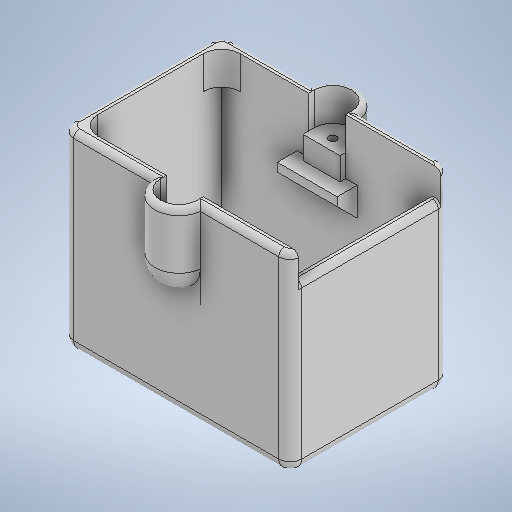
# Autodesk Inventor part: Lehmän laturi
Saved by Autodesk Inventor 2025.1 (Build 291241000, 241)
## iProperties
Created: 2025-09-19
Part Number: Lehmän laturi
Material: Generic
Document SubType Name: Modeling
Designer: totoikka
Density: 1 g/cm^3
Appearance: Default
Author: totoikka
Autodesk Inventor part; units mm, degrees
ref_plane "YZ Plane" through (0, 0, 0) normal (1, 0, 0) x (0, 1, 0)
ref_plane "XZ Plane" through (0, 0, 0) normal (0, 1, 0) x (-1, 0, 0)
ref_plane "XY Plane" through (0, 0, 0) normal (0, 0, 1) x (1, 0, 0)
sketch "Sketch1" plane through (0, 0, 0) normal (0, 1, 0) x (-1, 0, 0)
  line L0 (0, 0) -> (0, -66)
  line L1 (0, -33) -> (0, -60)
  line L2 (0, -60) -> (0, -6)
  circle A0 centre (0, -6) radius 1.375
  circle A1 centre (0, -60) radius 1.375
  circle A2 centre (0, -6) radius 6
  circle A3 centre (0, -60) radius 6
  line L3 (0, -33) -> (0, -57.5)
  line L4 (0, -57.5) -> (0, -8.5)
  line L5 (6, -6) -> (6, -8.5)
  line L6 (-6, -6) -> (-6, -8.5)
  line L7 (6, -6) -> (6, -60)
  line L8 (-6, -6) -> (-6, -60)
  line L9 (-6, -8.5) -> (-36.5, -8.5)
  line L10 (-36.5, -8.5) -> (-36.5, -57.5)
  line L11 (-36.5, -57.5) -> (-6, -57.5)
  line L12 (6, -8.5) -> (30.5, -8.5)
  line L13 (6, -57.5) -> (30.5, -57.5)
  line L14 (-36.5, -33) -> (36.5, -33)
  line L15 (36.5, -33) -> (36.5, -14.5)
  line L16 (36.5, -14.5) -> (36.5, -51.5)
  arc A4 (36.5, -14.5) -> (30.5, -8.5) centre (30.5, -14.5) ccw
  arc A5 (30.5, -57.5) -> (36.5, -51.5) centre (30.5, -51.5) ccw
  line L17 (36.5, -33) -> (37, -33)
  line L18 (37, -33) -> (37, -51.5)
  line L19 (37, -51.5) -> (37, -14.5)
  line L20 (-36.5, -33) -> (-37, -33)
  line L21 (-37, -33) -> (-37, -58)
  line L22 (-37, -58) -> (-37, -8)
  line L23 (-37, -8) -> (-6.5, -8)
  line L24 (-6.5, -8) -> (-6.5, -6)
  line L25 (30.5, -8) -> (6.5, -8)
  line L26 (6.5, -8) -> (6.5, -6)
  arc A6 (6.5, -6) -> (-6.5, -6) centre (0, -6) ccw
  line L27 (-37, -58) -> (-6.5, -58)
  line L28 (30.5, -58) -> (6.5, -58)
  line L29 (6.5, -58) -> (6.5, -60)
  line L30 (-6.5, -58) -> (-6.5, -60)
  arc A7 (-6.5, -60) -> (6.5, -60) centre (0, -60) ccw
  arc A8 (37, -14.5) -> (30.5, -8) centre (30.5, -14.5) ccw
  arc A9 (30.5, -58) -> (37, -51.5) centre (30.5, -51.5) ccw
  dimension "d0" = 66
  dimension "d1" = 27
  dimension "d2" = 54
  dimension "d3" = 2.75
  dimension "d4" = 2.75
  dimension "d5" = 24.5
  dimension "d6" = 49
  dimension "d7" = 30.5
  dimension "d8" = 24.5
  dimension "d9" = 73
  dimension "d10" = 18.5
  dimension "d11" = 37
  dimension "d12" = 0.5
  dimension "d13" = 0.5
  dimension "d14" = 25
  dimension "d15" = 50
  dimension "d16" = 30.5
  dimension "d17" = 24
  dimension "d18" = 30.5
  dimension "d19" = 24
  constraints: 62 end point, 18 point on circle, 13 tangent, 11 point on line, 10 centre point, 9 perpendicular, 4 coincident, 3 vertical, 2 horizontal, 2 midpoint, 1 parallel
  measures "d0" distance of L0.start L0.end
  measures "d1" distance of L1.start L1.end
  measures "d2" distance of L1.end L2.end
  measures "d3" diameter of A0
  measures "d4" diameter of A1
  measures "d5" distance of L1.start L3.end
  measures "d6" distance of L3.end L4.end
  measures "d7" distance of L6.end L9.end
  measures "d8" distance of L5.end L12.end
  measures "d9" distance of L14.start L14.end
  measures "d10" distance of L14.end L15.end
  measures "d11" distance of L15.end L16.end
  measures "d12" distance of L14.end L17.end
  measures "d13" distance of L14.start L20.end
  measures "d14" distance of L20.end L21.end
  measures "d15" distance of L21.end L22.end
  measures "d16" distance of L22.end L23.end
  measures "d17" distance of L25.start L25.end
  measures "d18" distance of L21.end L27.end
  measures "d19" distance of L28.start L28.end
extrude "Extrusion1" add sketch "Sketch1" along normal blind 2 contours A2 L0 A0 | A2 L6 L9 L10 L20 L22 L23 L24 A6 L26 L25 A8 L19 L17 L15 A4 L12 L5 | L0 A0 A2 | L5 L7 L14 L0 A2 | A2 L0 L14 L8 L6 | L12 A4 L15 L14 L7 | L8 L14 L10 L9 | L14 L7 A3 L0 | L0 A3 L8 L14 | L14 L16 A5 L13 L7 | L8 L11 L10 L14 | A3 L0 A1 | L0 A1 A3 | L13 A5 L16 L17 L18 A9 L28 L29 A7 L30 L27 L21 L20 L10 L11 L8 A3 L7
sketch "Sketch2" plane through (0, 2, 0) normal (0, 1, 0) x (1, 0, 0)
  line L0 (6.5, 8) -> (37, 8) projected
  line L1 (37, 8) -> (39, 8)
  line L2 (39, 8) -> (39, 58)
  line L3 (39, 58) -> (37, 58)
  line L4 (37, 58) -> (37, 8)
  point P0 (0, 0)
  dimension "d22" = 2
  constraints: 8 end point, 2 parallel, 1 horizontal, 1 perpendicular
  measures "d22" distance of L3.end L2.end
extrude "Extrusion2" add sketch "Sketch2" along normal blind 2
sketch "Sketch3" plane through (0, 2, 0) normal (0, 1, 0) x (1, 0, 0)
  line L0 (37, 8) -> (39, 8) projected
  arc A0 (-6.5, 6) -> (6.5, 6) centre (0, 6) ccw projected
  line L1 (39, 8) -> (6.5, 8)
  line L2 (6.5, 8) -> (6.5, 6)
  line L3 (6.5, 6) -> (39, 6)
  line L4 (39, 6) -> (39, 8)
  line L5 (39, 8) -> (39, 58) projected
  line L6 (6.5, 58) -> (6.5, 60) projected
  line L7 (39, 58) -> (6.5, 58)
  line L8 (6.5, 58) -> (6.5, 60)
  line L9 (6.5, 60) -> (39, 60)
  line L10 (39, 60) -> (39, 58)
  line L11 (-6.5, 8) -> (-6.5, 6) projected
  line L12 (-6.5, 8) -> (-39, 8)
  line L13 (-39, 8) -> (-39, 6)
  line L14 (-39, 6) -> (-6.5, 6)
  line L15 (-6.5, 6) -> (-6.5, 8)
  line L16 (-6.5, 60) -> (-6.5, 58) projected
  line L17 (-6.5, 58) -> (-39, 58)
  line L18 (-39, 58) -> (-39, 60)
  line L19 (-39, 60) -> (-6.5, 60)
  line L20 (-6.5, 60) -> (-6.5, 58)
  line L21 (-39, 8) -> (-37, 8)
  line L22 (-37, 8) -> (-37, 60)
  line L23 (-37, 60) -> (-39, 60)
  line L24 (-39, 60) -> (-39, 8)
  arc A1 (-37, 14.5) -> (-30.5, 8) centre (-30.5, 14.5) ccw projected
  arc A2 (-37, 14.5) -> (-30.5, 8) centre (-30.5, 14.5) ccw
  arc A3 (-30.5, 58) -> (-37, 51.5) centre (-30.5, 51.5) ccw projected
  arc A4 (-30.5, 58) -> (-37, 51.5) centre (-30.5, 51.5) ccw
  line L25 (0, -0.5) -> (0, -2.5)
  arc A5 (6.5, 60) -> (-6.5, 60) centre (0, 60) ccw projected
  line L26 (0, 66.5) -> (0, 68.5)
  line L27 (-6.5, 6) -> (-8.5, 6)
  line L28 (-8.5, 6) -> (-8.5, 60)
  line L29 (6.5, 6) -> (8.5, 6)
  line L30 (8.5, 6) -> (8.5, 60)
  arc A6 (-8.5, 6) -> (8.5, 6) centre (0, 6) ccw
  arc A7 (8.5, 60) -> (-8.5, 60) centre (0, 60) ccw
  point P0 (0, 0)
  dimension "d25" = 32.5
  dimension "d26" = 2
  dimension "d27" = 2
  dimension "d28" = 2
  dimension "d29" = 2
  dimension "d30" = 2
  constraints: 52 end point, 13 point on circle, 10 parallel, 7 perpendicular, 6 point on line, 5 horizontal, 4 centre point, 2 tangent, 2 vertical
  measures "d25" distance of L14.end L13.end
  measures "d26" distance of L23.end L22.end
  measures "d27" distance of L25.start L25.end
  measures "d28" distance of L26.start L26.end
  measures "d29" distance of L14.end L27.end
  measures "d30" distance of L2.end L29.end
extrude "Extrusion3" add sketch "Sketch3" along normal blind 11.5 contours L0 L4 L3 L30 L1 | L30 L3 L2 L1 | L7 L30 L9 L10 | A6 L25 A0 L3 | L7 L6 L9 L30 | A6 L14 A0 L25 | L9 A5 L26 A7 | L28 L12 L11 L14 | L14 L13 L12 L28 | L26 A5 L19 A7 | L28 L17 L22 L19 | L19 L16 L17 L28 | L24 L17 L22 L12 | L12 L22 A1 | L22 L17 L18 L19 | A3 L22 L17
sketch "Sketch4" plane through (0, 0, 0) normal (0, -1, 0) x (1, 0, 0)
  line L0 (37, -58) -> (37, -8) projected
  line L1 (-30.5, -8) -> (-6.5, -8) projected
  line L2 (37, -8) -> (-30.5, -8)
  line L3 (37, -8) -> (37, -58)
  line L4 (-37, -14.5) -> (-37, -51.5) projected
  line L5 (-37, -14.5) -> (-37, -51.5)
  arc A0 (-30.5, -8) -> (-37, -14.5) centre (-30.5, -14.5) ccw
  arc A1 (-37, -51.5) -> (-30.5, -58) centre (-30.5, -51.5) ccw projected
  arc A2 (-37, -51.5) -> (-37, -51.5) centre (-30.5, -51.5) ccw
  line L6 (37, -58) -> (6.5, -58) projected
  line L7 (-30.5, -58) -> (37, -58)
  line L8 (37, -58) -> (37, -8)
  point P0 (0, 0)
  constraints: 10 end point, 4 collinear, 2 point on circle, 2 tangent, 1 centre point, 1 horizontal alignment, 1 perpendicular, 1 vertical, 3 other
extrude "Extrusion4" cut sketch "Sketch4" against normal blind 11.5
sketch "Sketch5" plane through (0, 2, 0) normal (0, -1, 0) x (1, 0, 0)
  arc A0 (8.5, -6) -> (-8.5, -6) centre (0, -6) ccw projected
  line L0 (8.5, -6) -> (8.5, -8)
  line L1 (6.5, -8) -> (37, -8) projected
  line L2 (-39, -6) -> (-8.5, -6) projected
  line L3 (-8.5, -6) -> (-8.5, -8)
  arc A1 (-8.5, -60) -> (8.5, -60) centre (0, -60) ccw projected
  line L4 (-8.5, -8) -> (-8.5, -60)
  line L5 (8.5, -8) -> (8.5, -60)
  line L6 (8.5, -8) -> (-8.5, -8)
  line L7 (-6.5, -58) -> (-30.5, -58) projected
  line L8 (-8.5, -58) -> (8.5, -58)
  line L9 (6.5, -8) -> (6.5, -6) projected
  line L10 (6.5, -6) -> (6.5, -8)
  line L11 (-6.5, -6) -> (-6.5, -8) projected
  line L12 (-6.5, -6) -> (-6.5, -8)
  line L13 (-6.5, -8) -> (-6.5, -60)
  line L14 (-6.5, -60) -> (6.5, -60)
  arc A2 (6.5, -6) -> (-6.5, -6) centre (0, -6) ccw projected
  arc A3 (6.5, -6) -> (-6.5, -6) centre (0, -6) ccw
  arc A4 (8.5, -6) -> (-8.5, -6) centre (0, -6) ccw
  line L15 (6.5, -60) -> (6.5, -58) projected
  arc A5 (-6.5, -60) -> (6.5, -60) centre (0, -60) ccw
  arc A6 (-8.5, -60) -> (8.5, -60) centre (0, -60) ccw
  point P0 (0, 0)
  constraints: 20 end point, 8 point on circle, 5 point on line, 5 tangent, 4 centre point, 4 vertical, 3 perpendicular, 2 collinear, 1 concentric
extrude "Extrusion5" add sketch "Sketch5" along normal up to surface (2 mm away) contours L0 L1 L9 A2 L11 L6 L3 A0 | L5 A1 L4 L7 L13 A5 L15 L8
sketch "Sketch6" plane through (0, 2, 0) normal (0, -1, 0) x (1, 0, 0)
  line L0 (-39, -6) -> (-8.5, -6) projected
  line L1 (-8.5, -6) -> (-10.5, -6)
  line L2 (-10.5, -6) -> (-10.5, -8)
  line L3 (-10.5, -8) -> (-8.5, -8)
  line L4 (-8.5, -8) -> (-8.5, -6)
  line L5 (8.5, -8) -> (8.5, -6) projected
  line L6 (8.5, -6) -> (39, -6) projected
  line L7 (8.5, -8) -> (10.5, -8)
  line L8 (10.5, -8) -> (10.5, -6)
  line L9 (10.5, -6) -> (8.5, -6)
  line L10 (8.5, -6) -> (8.5, -8)
  line L11 (-8.5, -60) -> (-8.5, -58) projected
  line L12 (-8.5, -60) -> (-39, -60) projected
  line L13 (-8.5, -58) -> (-10.5, -58)
  line L14 (-10.5, -58) -> (-10.5, -60)
  line L15 (-10.5, -60) -> (-8.5, -60)
  line L16 (-8.5, -60) -> (-8.5, -58)
  line L17 (8.5, -58) -> (10.5, -58)
  line L18 (10.5, -58) -> (10.5, -60)
  line L19 (10.5, -60) -> (8.5, -60)
  line L20 (8.5, -60) -> (8.5, -58)
  point P0 (0, 0)
  dimension "d37" = 2
  dimension "d38" = 2
  dimension "d39" = 2
  constraints: 32 end point, 8 parallel, 6 point on line, 4 horizontal, 4 perpendicular
  measures "d37" distance of L3.end L2.end
  measures "d38" distance of L2.end L1.end
  measures "d39" distance of L9.end L8.end
extrude "Extrusion6" add sketch "Sketch6" along normal blind 8
sketch "Sketch7" plane through (0, 0, 0) normal (0, -1, 0) x (1, 0, 0)
  line L0 (8.5, -6) -> (8.5, -8) projected
  line L1 (8.5, -6) -> (-8.5, -6)
  line L2 (-8.5, -6) -> (-8.5, -8)
  line L3 (-8.5, -8) -> (8.5, -8)
  line L4 (8.5, -8) -> (8.5, -6)
  line L5 (39, -60) -> (8.5, -60) projected
  line L6 (-8.5, -58) -> (8.5, -58)
  line L7 (8.5, -58) -> (8.5, -60)
  line L8 (8.5, -60) -> (-8.5, -60)
  line L9 (-8.5, -60) -> (-8.5, -58)
  circle A0 centre (0, -6) radius 1.375
  circle A1 centre (0, -60) radius 1.375 projected
  circle A2 centre (0, -60) radius 1.375
  point P0 (0, 0)
  point P1 (-1.375, -60)
  point P2 (1.375, -60)
  point P3 (1.375, -6)
  point P4 (-1.375, -6)
  constraints: 16 end point, 4 parallel, 2 centre point, 2 horizontal, 2 perpendicular, 1 coincident, 1 midpoint, 1 point on line
extrude "Extrusion7" add sketch "Sketch7" along normal up to surface (6 mm away) contours L0 L3 L2 L1 A0 | L6 L7 L8 A1 L9
sketch "Sketch8" plane through (0, 0, 0) normal (0, -1, 0) x (1, 0, 0)
  arc A0 (8.5, -6) -> (-8.5, -6) centre (0, -6) ccw projected
  line L0 (8.5, -6) -> (-8.5, -6)
  arc A1 (-8.5, -60) -> (8.5, -60) centre (0, -60) ccw projected
  line L1 (8.5, -60) -> (-8.5, -60)
  arc A2 (8.5, -6) -> (-8.5, -6) centre (0, -6) ccw
  circle A3 centre (0, -6) radius 1.375 projected
  arc A4 (1.375, -6) -> (-1.375, -6) centre (0, -6) ccw
  circle A5 centre (0, -60) radius 1.375 projected
  arc A6 (-1.375, -60) -> (1.375, -60) centre (0, -60) ccw
  arc A7 (-8.5, -60) -> (8.5, -60) centre (0, -60) ccw
  point P0 (0, 0)
  constraints: 12 point on circle, 4 centre point, 4 end point, 4 point on line, 2 concentric, 2 horizontal
extrude "Extrusion8" add sketch "Sketch8" along normal up to surface (6 mm away) contours L0 A3 A0 | L1 A5 A1
sketch "Sketch9" plane through (0, -6, 0) normal (0, -1, 0) x (1, 0, 0)
  line L0 (10.5, -8) -> (10.5, -6) projected
  line L1 (10.5, -8) -> (-10.5, -8)
  line L2 (-10.5, -8) -> (-10.5, -15)
  line L3 (-10.5, -15) -> (10.5, -15)
  line L4 (10.5, -15) -> (10.5, -8)
  line L5 (10.5, -58) -> (-10.5, -58) projected
  line L6 (10.5, -58) -> (-10.5, -58)
  line L7 (-10.5, -58) -> (-10.5, -51)
  line L8 (-10.5, -51) -> (10.5, -51)
  line L9 (10.5, -51) -> (10.5, -58)
  point P0 (0, 0)
  dimension "d46" = 21
  dimension "d47" = 7
  dimension "d48" = 21
  dimension "d49" = 7
  constraints: 16 end point, 4 parallel, 2 horizontal, 2 perpendicular
  measures "d46" distance of L3.end L2.end
  measures "d47" distance of L2.end L1.end
  measures "d48" distance of L7.end L8.end
  measures "d49" distance of L6.end L7.end
extrude "Extrusion9" add sketch "Sketch9" along normal blind 3
sketch "Sketch10" plane through (0, -6, 0) normal (0, -1, 0) x (1, 0, 0)
  arc A0 (8.5, -6) -> (-8.5, -6) centre (0, -6) ccw projected
  line L0 (8.5, -6) -> (-8.5, -6)
  arc A1 (8.5, -6) -> (-8.5, -6) centre (0, -6) ccw
  point P0 (0, 0)
  constraints: 2 end point, 2 point on circle, 1 centre point, 1 concentric, 1 horizontal
revolve "Revolution1" add sketch "Sketch10" angle 90 about axis through (8.5, -6, -6) along (1, 0, 0)
sketch "Sketch11" plane through (0, -6, 0) normal (0, -1, 0) x (1, 0, 0)
  arc A0 (-8.5, -60) -> (8.5, -60) centre (0, -60) ccw projected
  line L0 (8.5, -60) -> (-8.5, -60)
  arc A1 (-8.5, -60) -> (8.5, -60) centre (0, -60) ccw
  point P0 (0, 0)
  constraints: 2 end point, 2 point on circle, 1 centre point, 1 concentric, 1 horizontal
revolve "Revolution2" add sketch "Sketch11" angle 90 about axis through (8.5, -6, -60) along (-1, 0, 0)
sketch "Sketch12" plane through (0, 2, 0) normal (0, -1, 0) x (1, 0, 0)
  line L0 (39, -58) -> (39, -60) projected
  line L1 (-39, -60) -> (-39, -6) projected
  line L2 (39, -60) -> (-39, -60)
  line L3 (-39, -60) -> (-39, -6)
  line L4 (-39, -6) -> (39, -6)
  line L5 (39, -6) -> (39, -60)
  line L6 (37, -8) -> (37, -58) projected
  line L7 (37, -58) -> (-37, -58)
  line L8 (-37, -58) -> (-37, -8)
  line L9 (-37, -8) -> (37, -8)
  line L10 (37, -8) -> (37, -58)
  point P0 (0, 0)
  constraints: 16 end point, 4 parallel, 2 horizontal, 2 perpendicular
extrude "Extrusion10" add sketch "Sketch12" along normal blind 35
sketch "Sketch13" plane through (0, 2, 0) normal (0, 1, 0) x (1, 0, 0)
  line L0 (1.375, 6) -> (-1.375, 6) projected
  circle A0 centre (0, 6) radius 1.375
  arc A1 (1.375, 60) -> (-1.375, 60) centre (0, 60) ccw projected
  circle A2 centre (0, 60) radius 1.375
  point P0 (0, 0)
  constraints: 1 coincident, 1 horizontal alignment, 1 midpoint, 5 other
extrude "Extrusion11" cut sketch "Sketch13" against normal blind 8
sketch "Sketch14" plane through (0, 2, 0) normal (0, 1, 0) x (1, 0, 0)
  line L0 (6.5, 6) -> (6.5, 8) projected
  line L1 (6.5, 8) -> (-6.5, 8)
  line L2 (-6.5, 8) -> (-6.5, 10)
  line L3 (-6.5, 10) -> (6.5, 10)
  line L4 (6.5, 10) -> (6.5, 8)
  line L5 (-6.5, 58) -> (6.5, 58) projected
  line L6 (6.5, 58) -> (-6.5, 58)
  line L7 (-6.5, 58) -> (-6.5, 56)
  line L8 (-6.5, 56) -> (6.5, 56)
  line L9 (6.5, 56) -> (6.5, 58)
  point P0 (0, 0)
  dimension "d58" = 13
  dimension "d59" = 2
  dimension "d60" = 13
  dimension "d61" = 2
  constraints: 16 end point, 4 parallel, 2 horizontal, 2 perpendicular
  measures "d58" distance of L2.end L3.end
  measures "d59" distance of L1.end L2.end
  measures "d60" distance of L8.end L7.end
  measures "d61" distance of L7.end L6.end
extrude "Extrusion12" add sketch "Sketch14" against normal blind 8
sketch "Sketch15" plane through (0, -33, 0) normal (0, -1, 0) x (1, 0, 0)
  line L0 (39, -58) -> (39, -60) projected
  line L1 (-39, -6) -> (-8.5, -6) projected
  line L2 (39, -60) -> (-39, -60)
  line L3 (-39, -60) -> (-39, -6)
  line L4 (-39, -6) -> (39, -6)
  line L5 (39, -6) -> (39, -60)
  line L6 (40, -61) -> (-40, -61)
  line L7 (-40, -61) -> (-40, -5)
  line L8 (-40, -5) -> (40, -5)
  line L9 (40, -5) -> (40, -61)
  line L10 (40, -61) -> (-40, -5) construction
  line L11 (-40, -61) -> (40, -5) construction
  arc A0 (8.5, -6) -> (-8.5, -6) centre (0, -6) ccw projected
  arc A1 (8.5, -6) -> (-8.5, -6) centre (0, -6) ccw
  arc A2 (-8.5, -60) -> (8.5, -60) centre (0, -60) ccw projected
  arc A3 (-8.5, -60) -> (8.5, -60) centre (0, -60) ccw
  point P0 (0, 0)
  point P1 (0, -33)
  point P2 (-8.441, -5)
  point P3 (-8.441, -61)
  point P4 (8.441, -5)
  point P5 (8.441, -61)
  dimension "d67" = 80
  dimension "d68" = 56
  constraints: 20 end point, 4 parallel, 4 point on circle, 2 centre point, 2 horizontal, 2 midpoint, 2 perpendicular
  measures "d67" distance of L7.end L8.end
  measures "d68" distance of L6.end L7.end
extrude "Extrusion13" add sketch "Sketch15" against normal up to surface (37 mm away) contours L5 L4 A0 L8 L9 L6 A2 L2 L0 | A2 L6 L7 L8 A0 L1 L3 L2
sketch "Sketch16" plane through (0, -6, -60) normal (0, 0, -1) x (-1, 0, 0)
  arc A0 (-8.5, 0) -> (8.5, 0) centre (0, 0) ccw projected
  circle A1 centre (0, 0) radius 8.5
  line L0 (8.5, 0) -> (8.5, -27)
  line L1 (-8.5, -27) -> (-8.5, 0) projected
  line L2 (8.5, -27) -> (-8.5, -27)
  line L3 (-8.5, -27) -> (-8.5, 0)
  point P0 (0, 6)
  constraints: 6 end point, 2 perpendicular, 1 coincident, 1 horizontal alignment, 1 vertical, 2 other
extrude "Extrusion14" add sketch "Sketch16" along normal up to surface (1 mm away) contours A0 L0 L2 L1
sketch "Sketch17" plane through (0, -6, -6) normal (0, 0, 1) x (1, 0, 0)
  arc A0 (-8.441, -1) -> (8.441, -1) centre (0, 0) ccw projected
  line L0 (8.441, 0) -> (-8.441, 0) projected
  circle A1 centre (0, 0) radius 8.441
  line L1 (8.5, -27) -> (-8.5, -27) projected
  line L2 (8.441, 0) -> (8.5, -27)
  line L3 (8.5, -27) -> (-8.5, -27)
  line L4 (-8.5, -27) -> (-8.441, 0)
  point P0 (0, 6)
  constraints: 6 end point, 1 coincident, 1 collinear, 3 other
extrude "Extrusion15" add sketch "Sketch17" along normal up to surface (1 mm away) contours L2 L1 L4 A1
sketch "Sketch18" plane through (0, 4, 0) normal (0, 1, 0) x (1, 0, 0)
  line L0 (39, 6) -> (39, 8) projected
  line L1 (39, 8) -> (40, 8)
  line L2 (40, 61) -> (40, 5) projected
  line L3 (40, 8) -> (40, 5)
  line L4 (40, 5) -> (8.5, 5)
  line L5 (8.5, 6) -> (39, 6) projected
  line L6 (8.5, 6) -> (39, 6)
  line L7 (39, 6) -> (39, 8)
  line L8 (39, 58) -> (37, 58) projected
  line L9 (39, 58) -> (40, 58)
  line L10 (8.441, 61) -> (40, 61) projected
  line L11 (40, 58) -> (40, 61)
  line L12 (40, 61) -> (8.441, 61)
  line L13 (39, 60) -> (8.5, 60) projected
  line L14 (8.441, 61) -> (8.5, 60)
  line L15 (8.5, 60) -> (39, 60)
  line L16 (39, 60) -> (39, 58)
  line L17 (8.5, 5) -> (8.441, 5)
  arc A0 (-8.5, 6) -> (8.5, 6) centre (0, 6) ccw projected
  line L18 (8.441, 5) -> (8.5, 6)
  point P0 (0, 0)
  constraints: 26 end point, 5 perpendicular, 3 collinear, 2 horizontal, 2 point on line
extrude "Extrusion16" add sketch "Sketch18" along normal up to surface (9.5 mm away) contours L0 L1 L2 L4 L17 A0 L5 | L2 L9 L16 L13 L14 L10
sketch "Sketch19" plane through (-40, 4, -61) normal (0, 1, 0) x (1, 0, 0)
  line L0 (80, -56) -> (0, -56) projected
  line L1 (0, 0) -> (80, 0) projected
  line L2 (0, -56) -> (0, 0)
  line L3 (0, 0) -> (31.559, 0)
  arc A0 (48.441, 0) -> (31.559, 0) centre (40, -1) ccw projected
  line L4 (0, -56) -> (31.559, -56)
  arc A1 (31.5, -55) -> (48.441, -56) centre (40, -55) ccw projected
  line L5 (1, -1) -> (1, -55) projected
  line L6 (31.5, -55) -> (1, -55)
  line L7 (1, -55) -> (1, -1)
  arc A2 (31.559, 0) -> (31.5, -1) centre (40, -1) ccw projected
  line L8 (1, -1) -> (31.5, -1)
  line L9 (31.5, -1) -> (31.559, 0)
  line L10 (31.559, -56) -> (31.5, -55)
  point P0 (40, -61)
  constraints: 16 end point, 3 perpendicular, 2 equal length, 2 point on circle, 1 vertical
extrude "Extrusion17" add sketch "Sketch19" along normal up to surface (9.5 mm away) contours L0 L2 L1 A2 L8 L5 L6 A1
sketch "Sketch20" plane through (0, -33, 0) normal (0, -1, 0) x (1, 0, 0)
  line L0 (-40, -5) -> (-40, -61) projected
  line L1 (40, -8) -> (40, -5) projected
  line L2 (-40, -61) -> (40, -61)
  line L3 (40, -61) -> (40, -5)
  line L4 (40, -5) -> (-40, -5)
  line L5 (-40, -5) -> (-40, -61)
  line L6 (37, -8) -> (37, -58) projected
  line L7 (-37, -8) -> (37, -8) projected
  line L8 (37, -58) -> (-37, -58)
  line L9 (-37, -58) -> (-37, -8)
  line L10 (-37, -8) -> (37, -8)
  line L11 (37, -8) -> (37, -58)
  point P0 (0, 0)
  constraints: 16 end point, 4 parallel, 2 horizontal, 2 perpendicular
extrude "Extrusion18" add sketch "Sketch20" along normal blind 3
sketch "Sketch21" plane through (-40, 13.5, -61) normal (-1, 0, 0) x (0, 0, 1)
  line L0 (3, -49.5) -> (53, -49.5) projected
  line L1 (14, -62) -> (42, -62)
  line L2 (42, -62) -> (42, -49.5)
  line L3 (42, -49.5) -> (14, -49.5)
  line L4 (14, -49.5) -> (14, -62)
  line L5 (28, -49.5) -> (28, -55.75)
  line L6 (56, 0) -> (56, -49.5) projected
  line L7 (56, -49.5) -> (0, -49.5)
  line L8 (0, -49.5) -> (0, -64.5)
  line L9 (0, -64.5) -> (56, -64.5)
  line L10 (56, -64.5) -> (56, -49.5)
  point P0 (61, -13.5)
  point P1 (14, -49.5)
  dimension "d81" = 28
  dimension "d82" = 12.5
  dimension "d83" = 56
  dimension "d84" = 15
  constraints: 18 end point, 4 parallel, 2 horizontal, 2 perpendicular, 1 midpoint, 1 vertical
  measures "d81" distance of L3.end L2.end
  measures "d82" distance of L2.end L1.end
  measures "d83" distance of L9.end L8.end
  measures "d84" distance of L8.end L7.end
extrude "Extrusion19" add sketch "Sketch21" against normal blind 3 contours L0 L4 L1 L2 L7 L10 L9 L8
sketch "Sketch22" plane through (-40, 13.5, -61) normal (-1, 0, 0) x (0, 0, 1)
  line L0 (42, -49.5) -> (42, -62) projected
  line L1 (14, -62) -> (14, -49.5) projected
  line L2 (42, -62) -> (14, -49.5)
  line L3 (14, -49.5) -> (42, -49.5)
  line L4 (14, -62) -> (42, -62) projected
  line L5 (42, -49.5) -> (14, -62)
  line L6 (43, -48.25) -> (13, -48.25)
  line L7 (13, -48.25) -> (13, -63.25)
  line L8 (13, -63.25) -> (43, -63.25)
  line L9 (43, -63.25) -> (43, -48.25)
  line L10 (43, -48.25) -> (13, -63.25) construction
  line L11 (13, -48.25) -> (43, -63.25) construction
  point P0 (61, -13.5)
  point P1 (28, -55.75)
  dimension "d87" = 30
  dimension "d88" = 15
  constraints: 18 end point, 3 midpoint, 2 parallel, 2 perpendicular, 1 horizontal
  measures "d87" distance of L8.end L7.end
  measures "d88" distance of L7.end L6.end
extrude "Extrusion20" cut sketch "Sketch22" against normal blind 2
sketch "Sketch23" plane through (-40, -51, -61) normal (0, -1, 0) x (1, 0, 0)
  line L0 (0, 0) -> (0, 56) projected
  line L1 (48.441, 0) -> (80, 0) projected
  line L2 (0, 56) -> (80, 56)
  line L3 (80, 56) -> (80, 0)
  line L4 (80, 0) -> (0, 0)
  line L5 (0, 0) -> (0, 56)
  point P0 (40, 61)
  constraints: 8 end point, 2 parallel, 1 horizontal, 1 perpendicular
extrude "Extrusion21" add sketch "Sketch23" along normal blind 3
sketch "Sketch24" plane through (-40, -54, -61) normal (0, -1, 0) x (1, 0, 0)
  line L0 (80, 0) -> (80, 56) projected
  line L1 (0, 0) -> (80, 0) projected
  line L2 (80, 56) -> (0, 0)
  line L3 (0, 0) -> (0, 56)
  line L4 (3, 56) -> (3, 0) projected
  line L5 (48.441, 0) -> (80, 0) projected
  line L6 (0, 56) -> (80, 0)
  circle A0 centre (40, 28) radius 3.25
  point P0 (40, 61)
  dimension "d93" = 6.5
  constraints: 6 end point, 1 centre point, 1 midpoint, 1 parallel
  measures "d93" diameter of A0
extrude "Extrusion22" cut sketch "Sketch24" against normal blind 3 contours A0 L2 L6 | L6 L2 A0 | L2 L6 A0 | L2 A0 L6
sketch "Sketch25" plane through (-40, -54, -61) normal (0, -1, 0) x (1, 0, 0)
  circle A0 centre (40, 28) radius 3.25 projected
  circle A1 centre (40, 28) radius 6
  point P0 (40, 61)
  dimension "d96" = 12
  constraints: 1 centre point, 1 coincident
  measures "d96" diameter of A1
extrude "Extrusion23" cut sketch "Sketch25" against normal blind 2
chamfer "Chamfer2" distance 2 angle 45 1 edges at (-6, -54, -33)
sketch "Sketch26" plane through (-8.441, 13.5, -61) normal (0, 0, -1) x (-1, 0, 0)
  line L0 (28.559, -49.5) -> (28.559, -64.5) projected
  line L1 (-48.441, 0) -> (-48.441, -49.5) projected
  line L2 (28.559, -64.5) -> (-48.441, -64.5)
  line L3 (-48.441, -64.5) -> (-48.441, -49.5)
  line L4 (-48.441, -49.5) -> (28.559, -49.5)
  line L5 (28.559, -49.5) -> (28.559, -64.5)
  point P0 (-8.441, -13.5)
  constraints: 8 end point, 2 parallel, 1 horizontal, 1 perpendicular
extrude "Extrusion24" add sketch "Sketch26" against normal blind 3
sketch "Sketch27" plane through (-40, 13.5, -5) normal (0, 0, 1) x (1, 0, 0)
  line L0 (80, -49.5) -> (3, -49.5) projected
  line L1 (80, -64.5) -> (3, -64.5) projected
  line L2 (3, -49.5) -> (80, -49.5)
  line L3 (80, -49.5) -> (80, -64.5)
  line L4 (80, -64.5) -> (3, -64.5)
  line L5 (3, -64.5) -> (3, -49.5)
  point P0 (40, -13.5)
  point P1 (3, -64.5)
  constraints: 8 end point, 2 parallel, 1 horizontal, 1 perpendicular
extrude "Extrusion25" add sketch "Sketch27" against normal blind 3
sketch "Sketch28" plane through (40, 4, -58) normal (1, 0, 0) x (0, 0, -1)
  line L0 (0, -40) -> (-50, -40) projected
  line L1 (0, -55) -> (-50, -55) projected
  line L2 (-50, -40) -> (0, -40)
  line L3 (0, -40) -> (0, -55)
  line L4 (0, -55) -> (-50, -55)
  line L5 (-50, -55) -> (-50, -40)
  point P0 (-58, -4)
  constraints: 8 end point, 2 parallel, 1 horizontal, 1 perpendicular
extrude "Extrusion26" add sketch "Sketch28" against normal blind 3
sketch "Sketch30" plane through (-40, -54, -61) normal (-1, 0, 0) x (0, 0, 1)
  line L0 (41.1924, 22.9343) -> (-9.5632, 22.9343) construction
  line L1 (-9.5632, 22.9343) -> (-9.5632, 39.0108) construction
  line L2 (-9.5632, 39.0108) -> (41.1924, 39.0108) construction
  line L3 (41.1924, 39.0108) -> (41.1924, 22.9343) construction
  line L4 (37.9624, 25.7594) -> (37.1093, 26.0283)
  spline S0 degree 2 poles (37.1093, 26.0283) (37.3051, 26.742) (38.218, 27.4358) (38.9185, 27.4358) knots 0 0 0 1 2 2 2
  spline S1 degree 2 poles (38.9185, 27.4358) (39.7849, 27.4358) (40.9036, 26.2507) (40.9036, 25.2249) knots 0 0 0 1 2 2 2
  spline S2 degree 2 poles (40.9036, 25.2249) (40.9036, 24.136) (39.7816, 22.9343) (38.8654, 22.9343) knots 0 0 0 1 2 2 2
  spline S3 degree 2 poles (38.8654, 22.9343) (38.0686, 22.9343) (37.5674, 23.4057) knots 0 0 0 1 1 1
  spline S4 degree 2 poles (37.5674, 23.4057) (37.2719, 23.6846) (37.1225, 24.2058) knots 0 0 0 1 1 1
  line L5 (37.1225, 24.2058) -> (37.9923, 24.4149)
  spline S5 degree 2 poles (37.9923, 24.4149) (38.0686, 24.0763) (38.56, 23.6846) (38.9085, 23.6846) knots 0 0 0 1 2 2 2
  spline S6 degree 2 poles (38.9085, 23.6846) (39.3932, 23.6846) (39.9974, 24.3784) (39.9974, 25.1585) knots 0 0 0 1 2 2 2
  spline S7 degree 2 poles (39.9974, 25.1585) (39.9974, 25.9851) (39.4031, 26.6855) (38.9284, 26.6855) knots 0 0 0 1 2 2 2
  spline S8 degree 2 poles (38.9284, 26.6855) (38.5766, 26.6855) (38.072, 26.2374) (37.9624, 25.7594) knots 0 0 0 1 2 2 2
  line L6 (36.3524, 27.3628) -> (36.3524, 23.0074)
  line L7 (36.3524, 23.0074) -> (35.4727, 23.0074)
  line L8 (35.4727, 23.0074) -> (35.4727, 24.7203)
  line L9 (35.4727, 24.7203) -> (33.7498, 24.7203)
  line L10 (33.7498, 24.7203) -> (33.7498, 23.0074)
  line L11 (33.7498, 23.0074) -> (32.87, 23.0074)
  line L12 (32.87, 23.0074) -> (32.87, 27.3628)
  line L13 (32.87, 27.3628) -> (33.7498, 27.3628)
  line L14 (33.7498, 27.3628) -> (33.7498, 25.4573)
  line L15 (33.7498, 25.4573) -> (35.4727, 25.4573)
  line L16 (35.4727, 25.4573) -> (35.4727, 27.3628)
  line L17 (35.4727, 27.3628) -> (36.3524, 27.3628)
  line L18 (28.0333, 27.3628) -> (28.9894, 27.3628)
  line L19 (28.9894, 27.3628) -> (29.3678, 26.3735)
  line L20 (29.3678, 26.3735) -> (31.1073, 26.3735)
  line L21 (31.1073, 26.3735) -> (31.4692, 27.3628)
  line L22 (31.4692, 27.3628) -> (32.402, 27.3628)
  line L23 (32.402, 27.3628) -> (30.7089, 23.0074)
  line L24 (30.7089, 23.0074) -> (29.7728, 23.0074)
  line L25 (29.7728, 23.0074) -> (28.0333, 27.3628)
  line L26 (29.65, 25.6365) -> (30.2508, 24.0232)
  line L27 (30.2508, 24.0232) -> (30.8417, 25.6365)
  line L28 (30.8417, 25.6365) -> (29.65, 25.6365)
  line L29 (27.5619, 27.3628) -> (27.5619, 23.0074)
  line L30 (27.5619, 23.0074) -> (25.7095, 23.0074)
  spline S9 degree 2 poles (25.7095, 23.0074) (25.0091, 23.0074) (24.3783, 23.2431) (23.9966, 23.8406) (23.9966, 24.229) knots 0 0 0 1 2 3 3 3
  spline S10 degree 2 poles (23.9966, 24.229) (23.9966, 24.717) (24.5709, 25.3577) (25.1452, 25.4407) knots 0 0 0 1 2 2 2
  spline S11 degree 2 poles (25.1452, 25.4407) (24.8597, 25.6067) (24.4879, 26.005) (24.1725, 26.5129) knots 0 0 0 1 2 2 2
  line L31 (24.1725, 26.5129) -> (23.6414, 27.3628)
  line L32 (23.6414, 27.3628) -> (24.6937, 27.3628)
  line L33 (24.6937, 27.3628) -> (25.3278, 26.4133)
  spline S12 degree 2 poles (25.3278, 26.4133) (25.6697, 25.9054) (25.9187, 25.6399) (26.1975, 25.5436) (26.5029, 25.5436) knots 0 0 0 1 2 3 3 3
  line L34 (26.5029, 25.5436) -> (26.6822, 25.5436)
  line L35 (26.6822, 25.5436) -> (26.6822, 27.3628)
  line L36 (26.6822, 27.3628) -> (27.5619, 27.3628)
  line L37 (26.6822, 24.8498) -> (26.0315, 24.8498)
  spline S13 degree 2 poles (26.0315, 24.8498) (25.3975, 24.8498) (25.0821, 24.7435) (24.9029, 24.4813) (24.9029, 24.2854) knots 0 0 0 1 2 3 3 3
  spline S14 degree 2 poles (24.9029, 24.2854) (24.9029, 24.0663) (25.1385, 23.7941) (25.351, 23.7576) knots 0 0 0 1 2 2 2
  spline S15 degree 2 poles (25.351, 23.7576) (25.4606, 23.7443) (25.995, 23.7443) knots 0 0 0 1 1 1
  line L38 (25.995, 23.7443) -> (26.6822, 23.7443)
  line L39 (26.6822, 23.7443) -> (26.6822, 24.8498)
  line L40 (21.1417, 25.766) -> (21.1417, 25.029)
  line L41 (21.1417, 25.029) -> (19.2461, 25.029)
  line L42 (19.2461, 25.029) -> (19.2461, 26.7619)
  spline S16 degree 2 poles (19.2461, 26.7619) (19.5217, 27.0308) (20.5707, 27.4358) (21.1085, 27.4358) knots 0 0 0 1 2 2 2
  spline S17 degree 2 poles (21.1085, 27.4358) (21.7923, 27.4358) (22.8081, 26.8615) (23.3194, 25.7959) (23.3194, 25.1718) knots 0 0 0 1 2 3 3 3
  spline S18 degree 2 poles (23.3194, 25.1718) (23.3194, 24.4912) (22.7484, 23.4323) (22.2006, 23.1501) knots 0 0 0 1 2 2 2
  spline S19 degree 2 poles (22.2006, 23.1501) (21.779, 22.9343) (21.155, 22.9343) knots 0 0 0 1 1 1
  spline S20 degree 2 poles (21.155, 22.9343) (20.345, 22.9343) (19.432, 23.6149) (19.3026, 24.2157) knots 0 0 0 1 2 2 2
  line L43 (19.3026, 24.2157) -> (20.1757, 24.3784)
  spline S21 degree 2 poles (20.1757, 24.3784) (20.2686, 24.0564) (20.7765, 23.6846) (21.155, 23.6846) knots 0 0 0 1 2 2 2
  spline S22 degree 2 poles (21.155, 23.6846) (21.7326, 23.6846) (22.4131, 24.4149) (22.4131, 25.1353) knots 0 0 0 1 2 2 2
  spline S23 degree 2 poles (22.4131, 25.1353) (22.4131, 25.9087) (21.7226, 26.6855) (21.1649, 26.6855) knots 0 0 0 1 2 2 2
  spline S24 degree 2 poles (21.1649, 26.6855) (20.8894, 26.6855) (20.335, 26.4698) (20.1358, 26.3171) knots 0 0 0 1 2 2 2
  line L44 (20.1358, 26.3171) -> (20.1358, 25.766)
  line L45 (20.1358, 25.766) -> (21.1417, 25.766)
  line L46 (18.4328, 27.3628) -> (18.4328, 23.0074)
  line L47 (18.4328, 23.0074) -> (15.2028, 23.0074)
  line L48 (15.2028, 23.0074) -> (15.2028, 23.7443)
  line L49 (15.2028, 23.7443) -> (17.5531, 23.7443)
  line L50 (17.5531, 23.7443) -> (17.5531, 24.7103)
  line L51 (17.5531, 24.7103) -> (15.3655, 24.7103)
  line L52 (15.3655, 24.7103) -> (15.3655, 25.4473)
  line L53 (15.3655, 25.4473) -> (17.5531, 25.4473)
  line L54 (17.5531, 25.4473) -> (17.5531, 26.6258)
  line L55 (17.5531, 26.6258) -> (15.1198, 26.6258)
  line L56 (15.1198, 26.6258) -> (15.1198, 27.3628)
  line L57 (15.1198, 27.3628) -> (18.4328, 27.3628)
  point P0 (61, 54)
  constraints: 2 other
extrude "Extrusion28" cut sketch "Sketch30" against normal blind 1.5
sketch "Sketch31" plane through (-40, -54, -61) normal (0, -1, 0) x (1, 0, 0)
  line L0 (49.685, 18.5111) -> (49.685, 28.4224) construction
  line L1 (49.685, 28.4224) -> (112.3065, 28.4224) construction
  line L2 (112.3065, 28.4224) -> (112.3065, 18.5111) construction
  line L3 (112.3065, 18.5111) -> (49.685, 18.5111) construction
  circle A0 centre (40, 28) radius 8 projected
  line L4 (40, 36) -> (63.1505, 36)
  line L5 (40, 20) -> (63.7324, 20)
  line L6 (53.7506, 18.9195) -> (49.7521, 18.9195)
  line L7 (49.7521, 18.9195) -> (49.7521, 20.6201)
  spline S0 degree 2 poles (49.7521, 20.6201) (49.7521, 21.2631) (49.9685, 21.8422) (50.5171, 22.1927) (50.8736, 22.1927) knots 0 0 0 1 2 3 3 3
  spline S1 degree 2 poles (50.8736, 22.1927) (51.3216, 22.1927) (51.9098, 21.6654) (51.986, 21.1382) knots 0 0 0 1 2 2 2
  spline S2 degree 2 poles (51.986, 21.1382) (52.1384, 21.4003) (52.5041, 21.7416) (52.9704, 22.0311) knots 0 0 0 1 2 2 2
  line L8 (52.9704, 22.0311) -> (53.7506, 22.5188)
  line L9 (53.7506, 22.5188) -> (53.7506, 21.5527)
  line L10 (53.7506, 21.5527) -> (52.879, 20.9705)
  spline S3 degree 2 poles (52.879, 20.9705) (52.4127, 20.6566) (52.1689, 20.4281) (52.0805, 20.1721) (52.0805, 19.8917) knots 0 0 0 1 2 3 3 3
  line L11 (52.0805, 19.8917) -> (52.0805, 19.7271)
  line L12 (52.0805, 19.7271) -> (53.7506, 19.7271)
  line L13 (53.7506, 19.7271) -> (53.7506, 18.9195)
  line L14 (51.4436, 19.7271) -> (51.4436, 20.3244)
  spline S4 degree 2 poles (51.4436, 20.3244) (51.4436, 20.9065) (51.346, 21.1961) (51.1053, 21.3606) (50.9254, 21.3606) knots 0 0 0 1 2 3 3 3
  spline S5 degree 2 poles (50.9254, 21.3606) (50.7243, 21.3606) (50.4744, 21.1443) (50.4409, 20.9492) knots 0 0 0 1 2 2 2
  spline S6 degree 2 poles (50.4409, 20.9492) (50.4287, 20.8486) (50.4287, 20.358) knots 0 0 0 1 1 1
  line L15 (50.4287, 20.358) -> (50.4287, 19.7271)
  line L16 (50.4287, 19.7271) -> (51.4436, 19.7271)
  line L17 (53.7506, 22.9546) -> (49.7521, 22.9546)
  line L18 (49.7521, 22.9546) -> (49.7521, 25.92)
  line L19 (49.7521, 25.92) -> (50.4287, 25.92)
  line L20 (50.4287, 25.92) -> (50.4287, 23.7622)
  line L21 (50.4287, 23.7622) -> (51.3155, 23.7622)
  line L22 (51.3155, 23.7622) -> (51.3155, 25.7706)
  line L23 (51.3155, 25.7706) -> (51.9921, 25.7706)
  line L24 (51.9921, 25.7706) -> (51.9921, 23.7622)
  line L25 (51.9921, 23.7622) -> (53.0741, 23.7622)
  line L26 (53.0741, 23.7622) -> (53.0741, 25.9962)
  line L27 (53.0741, 25.9962) -> (53.7506, 25.9962)
  line L28 (53.7506, 25.9962) -> (53.7506, 22.9546)
  line L29 (52.4462, 26.4746) -> (52.37, 27.2609)
  spline S7 degree 2 poles (52.37, 27.2609) (52.7662, 27.331) (53.1381, 27.7669) (53.1381, 28.1326) knots 0 0 0 1 2 2 2
  spline S8 degree 2 poles (53.1381, 28.1326) (53.1381, 28.5227) (52.8089, 28.9189) (52.5864, 28.9189) knots 0 0 0 1 2 2 2
  spline S9 degree 2 poles (52.5864, 28.9189) (52.4432, 28.9189) (52.2451, 28.7513) (52.1719, 28.544) knots 0 0 0 1 2 2 2
  spline S10 degree 2 poles (52.1719, 28.544) (52.1232, 28.4038) (51.9982, 27.8979) knots 0 0 0 1 1 1
  spline S11 degree 2 poles (51.9982, 27.8979) (51.8367, 27.2488) (51.602, 26.9867) knots 0 0 0 1 1 1
  spline S12 degree 2 poles (51.602, 26.9867) (51.2729, 26.6179) (50.8005, 26.6179) knots 0 0 0 1 1 1
  spline S13 degree 2 poles (50.8005, 26.6179) (50.4927, 26.6179) (49.9624, 26.9653) (49.685, 27.6175) (49.685, 28.0777) knots 0 0 0 1 2 3 3 3
  spline S14 degree 2 poles (49.685, 28.0777) (49.685, 28.8305) (50.3433, 29.5924) (50.895, 29.6107) knots 0 0 0 1 2 2 2
  line L30 (50.895, 29.6107) -> (50.9315, 28.8031)
  spline S15 degree 2 poles (50.9315, 28.8031) (50.6237, 28.7513) (50.3525, 28.4099) (50.3525, 28.0686) knots 0 0 0 1 2 2 2
  spline S16 degree 2 poles (50.3525, 28.0686) (50.3525, 27.7151) (50.4957, 27.517) knots 0 0 0 1 1 1
  spline S17 degree 2 poles (50.4957, 27.517) (50.5902, 27.3889) (50.7456, 27.3889) knots 0 0 0 1 1 1
  spline S18 degree 2 poles (50.7456, 27.3889) (50.8858, 27.3889) (50.9894, 27.5078) knots 0 0 0 1 1 1
  spline S19 degree 2 poles (50.9894, 27.5078) (51.1174, 27.6632) (51.3948, 28.8427) (51.6904, 29.4065) (52.2055, 29.7265) (52.5864, 29.7265) knots 0 0 0 1 2 3 4 4 4
  spline S20 degree 2 poles (52.5864, 29.7265) (52.9278, 29.7265) (53.5282, 29.3456) (53.8207, 28.6476) (53.8207, 28.1265) knots 0 0 0 1 2 3 3 3
  spline S21 degree 2 poles (53.8207, 28.1265) (53.8207, 27.3676) (53.1198, 26.5539) (52.4462, 26.4746) knots 0 0 0 1 2 2 2
  line L31 (53.7506, 30.4092) -> (49.7521, 30.4092)
  line L32 (49.7521, 30.4092) -> (49.7521, 33.3746)
  line L33 (49.7521, 33.3746) -> (50.4287, 33.3746)
  line L34 (50.4287, 33.3746) -> (50.4287, 31.2168)
  line L35 (50.4287, 31.2168) -> (51.3155, 31.2168)
  line L36 (51.3155, 31.2168) -> (51.3155, 33.2252)
  line L37 (51.3155, 33.2252) -> (51.9921, 33.2252)
  line L38 (51.9921, 33.2252) -> (51.9921, 31.2168)
  line L39 (51.9921, 31.2168) -> (53.0741, 31.2168)
  line L40 (53.0741, 31.2168) -> (53.0741, 33.4508)
  line L41 (53.0741, 33.4508) -> (53.7506, 33.4508)
  line L42 (53.7506, 33.4508) -> (53.7506, 30.4092)
  line L43 (53.7506, 35.0356) -> (50.4287, 35.0356)
  line L44 (50.4287, 35.0356) -> (50.4287, 33.85)
  line L45 (50.4287, 33.85) -> (49.7521, 33.85)
  line L46 (49.7521, 33.85) -> (49.7521, 37.0257)
  line L47 (49.7521, 37.0257) -> (50.4287, 37.0257)
  line L48 (50.4287, 37.0257) -> (50.4287, 35.8432)
  line L49 (50.4287, 35.8432) -> (53.7506, 35.8432)
  line L50 (53.7506, 35.8432) -> (53.7506, 35.0356)
  point P0 (40, 61)
  constraints: 4 end point, 2 horizontal, 2 point on circle, 1 tangent, 2 other
extrude "Extrusion29" cut sketch "Sketch31" against normal blind 1.5 contours L46 L47 L48 L4 | L4 L48 L49 L50 L43 L44 L45 L46 | L7 S0 S1 S2 L8 L9 L10 S3 L5 L14 S4 S5 S6 L15 | L5 L15 L16 L14 S3 L11 L12 L13 L6 L7 | L17 L18 L19 L20 L21 L22 L23 L24 L25 L26 L27 L28 | L29 S7 S8 S9 S10 S11 S12 S13 S14 L30 S15 S16 S17 S18 S19 S20 S21 | L31 L32 L33 L34 L35 L36 L37 L38 L39 L40 L41 L42
chamfer "Chamfer7" distance 2 angle 45 4 edges at (-40, -42.25, -18) (-40, -34.75, -33) (-40, -42.25, -48) (-40, -49.75, -33)
fillet "Fillet1" radius 4 8 edges at (0, -54, -61) (40, -54, -33) (40, -20.25, -61) (40, -20.25, -5) (-40, -20.25, -61) (-40, -20.25, -5) (0, -54, -5) (-40, -54, -33)
sketch "Sketch32" plane through (40, -50, -9) normal (1, 0, 0) x (0, 0, -1)
  line L0 (0, 52) -> (48, 52) projected
  line L1 (24, 52) -> (24, 7)
  line L2 (24, 7) -> (39, 7)
  line L3 (39, 7) -> (9, 7)
  circle A0 centre (39, 7) radius 2.5
  circle A1 centre (9, 7) radius 2.5
  point P0 (-9, 50)
  dimension "d133" = 45
  dimension "d134" = 15
  dimension "d135" = 30
  dimension "d136" = 5
  dimension "d137" = 5
  constraints: 6 end point, 2 centre point, 2 coincident, 1 midpoint, 1 perpendicular, 1 point on line, 1 vertical
  measures "d133" distance of L1.start L1.end
  measures "d134" distance of L1.end L2.end
  measures "d135" distance of L2.end L3.end
  measures "d136" diameter of A0
  measures "d137" diameter of A1
extrude "Extrusion30" cut sketch "Sketch32" against normal blind 10
sketch "Sketch33" plane through (40, -50, -9) normal (1, 0, 0) x (0, 0, -1)
  line L0 (16.5708, 10.2962) -> (-6.9144, 10.2962) construction
  line L1 (-6.9144, 10.2962) -> (-6.9144, 21.5426) construction
  line L2 (-6.9144, 21.5426) -> (16.5708, 21.5426) construction
  line L3 (16.5708, 21.5426) -> (16.5708, 10.2962) construction
  line L4 (14.4594, 14.1974) -> (15.1963, 14.1974)
  line L5 (15.1963, 14.1974) -> (15.1963, 11.428)
  spline S0 degree 2 poles (15.1963, 11.428) (15.5999, 11.8023) (16.1468, 11.9836) knots 0 0 0 1 1 1
  line L6 (16.1468, 11.9836) -> (16.1468, 11.3168)
  spline S1 degree 2 poles (16.1468, 11.3168) (15.8572, 11.2233) (15.1817, 10.6969) (15.0559, 10.3459) knots 0 0 0 1 2 2 2
  line L7 (15.0559, 10.3459) -> (14.4594, 10.3459)
  line L8 (14.4594, 10.3459) -> (14.4594, 14.1974)
  spline S2 degree 2 poles (12.1198, 10.3459) (11.5612, 10.3459) (11.2483, 10.7436) knots 0 0 0 1 1 1
  spline S3 degree 2 poles (11.2483, 10.7436) (10.874, 11.2145) (10.874, 12.3053) knots 0 0 0 1 1 1
  spline S4 degree 2 poles (10.874, 12.3053) (10.874, 13.3932) (11.2512, 13.8699) knots 0 0 0 1 1 1
  spline S5 degree 2 poles (11.2512, 13.8699) (11.5612, 14.2618) (12.1198, 14.2618) knots 0 0 0 1 1 1
  spline S6 degree 2 poles (12.1198, 14.2618) (12.6813, 14.2618) (13.3656, 13.402) (13.3656, 12.2965) knots 0 0 0 1 2 2 2
  spline S7 degree 2 poles (13.3656, 12.2965) (13.3656, 11.2145) (12.9883, 10.7378) knots 0 0 0 1 1 1
  spline S8 degree 2 poles (12.9883, 10.7378) (12.6784, 10.3459) (12.1198, 10.3459) knots 0 0 0 1 1 1
  spline S9 degree 2 poles (12.1198, 10.9571) (12.2543, 10.9571) (12.4619, 11.1268) (12.5204, 11.3461) knots 0 0 0 1 2 2 2
  spline S10 degree 2 poles (12.5204, 11.3461) (12.5965, 11.6298) (12.5965, 12.3053) knots 0 0 0 1 1 1
  spline S11 degree 2 poles (12.5965, 12.3053) (12.5965, 12.9779) (12.459, 13.4839) (12.2543, 13.6506) (12.1198, 13.6506) knots 0 0 0 1 2 3 3 3
  spline S12 degree 2 poles (12.1198, 13.6506) (11.9853, 13.6506) (11.7776, 13.4809) (11.7191, 13.2616) knots 0 0 0 1 2 2 2
  spline S13 degree 2 poles (11.7191, 13.2616) (11.6431, 12.9779) (11.6431, 12.3053) knots 0 0 0 1 1 1
  spline S14 degree 2 poles (11.6431, 12.3053) (11.6431, 11.6298) (11.7805, 11.1268) (11.9853, 10.9571) (12.1198, 10.9571) knots 0 0 0 1 2 3 3 3
  spline S15 degree 2 poles (9.1398, 10.3459) (8.5812, 10.3459) (8.2683, 10.7436) knots 0 0 0 1 1 1
  spline S16 degree 2 poles (8.2683, 10.7436) (7.8939, 11.2145) (7.8939, 12.3053) knots 0 0 0 1 1 1
  spline S17 degree 2 poles (7.8939, 12.3053) (7.8939, 13.3932) (8.2712, 13.8699) knots 0 0 0 1 1 1
  spline S18 degree 2 poles (8.2712, 13.8699) (8.5812, 14.2618) (9.1398, 14.2618) knots 0 0 0 1 1 1
  spline S19 degree 2 poles (9.1398, 14.2618) (9.7012, 14.2618) (10.3856, 13.402) (10.3856, 12.2965) knots 0 0 0 1 2 2 2
  spline S20 degree 2 poles (10.3856, 12.2965) (10.3856, 11.2145) (10.0083, 10.7378) knots 0 0 0 1 1 1
  spline S21 degree 2 poles (10.0083, 10.7378) (9.6983, 10.3459) (9.1398, 10.3459) knots 0 0 0 1 1 1
  spline S22 degree 2 poles (9.1398, 10.9571) (9.2743, 10.9571) (9.4819, 11.1268) (9.5404, 11.3461) knots 0 0 0 1 2 2 2
  spline S23 degree 2 poles (9.5404, 11.3461) (9.6164, 11.6298) (9.6164, 12.3053) knots 0 0 0 1 1 1
  spline S24 degree 2 poles (9.6164, 12.3053) (9.6164, 12.9779) (9.479, 13.4839) (9.2743, 13.6506) (9.1398, 13.6506) knots 0 0 0 1 2 3 3 3
  spline S25 degree 2 poles (9.1398, 13.6506) (9.0052, 13.6506) (8.7976, 13.4809) (8.7391, 13.2616) knots 0 0 0 1 2 2 2
  spline S26 degree 2 poles (8.7391, 13.2616) (8.6631, 12.9779) (8.6631, 12.3053) knots 0 0 0 1 1 1
  spline S27 degree 2 poles (8.6631, 12.3053) (8.6631, 11.6298) (8.8005, 11.1268) (9.0052, 10.9571) (9.1398, 10.9571) knots 0 0 0 1 2 3 3 3
  spline S28 degree 2 poles (3.3201, 13.3377) (3.3201, 12.82) (2.8668, 12.3229) (2.4749, 12.3229) knots 0 0 0 1 2 2 2
  spline S29 degree 2 poles (2.4749, 12.3229) (2.0801, 12.3229) (1.6268, 12.82) (1.6268, 13.3377) knots 0 0 0 1 2 2 2
  spline S30 degree 2 poles (1.6268, 13.3377) (1.6268, 13.8553) (2.0801, 14.3524) (2.4661, 14.3524) knots 0 0 0 1 2 2 2
  spline S31 degree 2 poles (2.4661, 14.3524) (2.8668, 14.3524) (3.3201, 13.8553) (3.3201, 13.3377) knots 0 0 0 1 2 2 2
  spline S32 degree 2 poles (5.9082, 11.3081) (5.9082, 10.7934) (5.4549, 10.2962) (5.0689, 10.2962) knots 0 0 0 1 2 2 2
  spline S33 degree 2 poles (5.0689, 10.2962) (4.6682, 10.2962) (4.2149, 10.7904) (4.2149, 11.3081) knots 0 0 0 1 2 2 2
  spline S34 degree 2 poles (4.2149, 11.3081) (4.2149, 11.8228) (4.6682, 12.3199) (5.0543, 12.3199) knots 0 0 0 1 2 2 2
  spline S35 degree 2 poles (5.0543, 12.3199) (5.4549, 12.3199) (5.9082, 11.8257) (5.9082, 11.3081) knots 0 0 0 1 2 2 2
  line L9 (4.5074, 14.3437) -> (5.0513, 14.3437)
  line L10 (5.0513, 14.3437) -> (3.0071, 10.2962)
  line L11 (3.0071, 10.2962) -> (2.4778, 10.2962)
  line L12 (2.4778, 10.2962) -> (4.5074, 14.3437)
  spline S36 degree 2 poles (2.7469, 13.3347) (2.7469, 13.7091) (2.6591, 13.8348) knots 0 0 0 1 1 1
  spline S37 degree 2 poles (2.6591, 13.8348) (2.5948, 13.9313) (2.4778, 13.9313) knots 0 0 0 1 1 1
  spline S38 degree 2 poles (2.4778, 13.9313) (2.3608, 13.9313) (2.2994, 13.8377) knots 0 0 0 1 1 1
  spline S39 degree 2 poles (2.2994, 13.8377) (2.2117, 13.7091) (2.2117, 13.3347) knots 0 0 0 1 1 1
  spline S40 degree 2 poles (2.2117, 13.3347) (2.2117, 12.9604) (2.2965, 12.8317) knots 0 0 0 1 1 1
  spline S41 degree 2 poles (2.2965, 12.8317) (2.3608, 12.7381) (2.4778, 12.7381) knots 0 0 0 1 1 1
  spline S42 degree 2 poles (2.4778, 12.7381) (2.5977, 12.7381) (2.6591, 12.8317) knots 0 0 0 1 1 1
  spline S43 degree 2 poles (2.6591, 12.8317) (2.7469, 12.9604) (2.7469, 13.3347) knots 0 0 0 1 1 1
  spline S44 degree 2 poles (5.335, 11.3022) (5.335, 11.6766) (5.2473, 11.8052) knots 0 0 0 1 1 1
  spline S45 degree 2 poles (5.2473, 11.8052) (5.1829, 11.8988) (5.066, 11.8988) knots 0 0 0 1 1 1
  spline S46 degree 2 poles (5.066, 11.8988) (4.949, 11.8988) (4.8847, 11.8052) knots 0 0 0 1 1 1
  spline S47 degree 2 poles (4.8847, 11.8052) (4.7998, 11.6766) (4.7998, 11.3022) knots 0 0 0 1 1 1
  spline S48 degree 2 poles (4.7998, 11.3022) (4.7998, 10.9308) (4.8847, 10.8051) knots 0 0 0 1 1 1
  spline S49 degree 2 poles (4.8847, 10.8051) (4.949, 10.7086) (5.066, 10.7086) knots 0 0 0 1 1 1
  spline S50 degree 2 poles (5.066, 10.7086) (5.1829, 10.7086) (5.2473, 10.8021) knots 0 0 0 1 1 1
  spline S51 degree 2 poles (5.2473, 10.8021) (5.335, 10.9308) (5.335, 11.3022) knots 0 0 0 1 1 1
  point P0 (-9, 50)
  constraints: 2 other
extrude "Extrusion31" cut sketch "Sketch33" against normal blind 1.5
sketch "Sketch34" plane through (40, -50, -9) normal (1, 0, 0) x (0, 0, -1)
  line L0 (0, -4) -> (0, 0) projected
  line L1 (0, 0) -> (42.8809, 0)
  line L2 (42.8809, 0) -> (42.8809, 26.5)
  line L3 (42.8809, 26.5) -> (0, 26.5)
  line L4 (0, 26.5) -> (0, 0)
  point P0 (-9, 50)
  constraints: 8 end point, 2 parallel, 1 horizontal, 1 perpendicular
extrude "Extrusion32" add sketch "Sketch34" against normal up to surface (3 mm away)
fillet "Fillet2" radius 2 11 edges at (-38.8284, 13.5, -6.1716) (-40, 13.5, -33) (-38.8284, 13.5, -59.8284) (-22.2205, 13.5, -61) (-22.2205, 13.5, -5) (0, 13.5, -68.5) (38.4495, 13.5, -60.1623) (22.2205, 13.5, -61) (38.4495, 13.5, -5.8377) (22.2205, 13.5, -5) (0, 13.5, 2.5)
fillet "Fillet3" radius 2 3 edges at (39.9681, 4, -8.496) (39.9681, 4, -57.504) (40, 4, -33)
sketch "Sketch35" plane through (10.5, -6, -51) normal (1, 0, 0) x (0, 0, -1)
  line L0 (7, -3) -> (0, -3) projected
  line L1 (7, 0) -> (7, -3) projected
  line L2 (0, -3) -> (7, -3)
  line L3 (7, -3) -> (7, -10)
  line L4 (7, -10) -> (0, -3)
  line L5 (-36, -3) -> (-43, -3) projected
  line L6 (-36, -3) -> (-43, -3)
  line L7 (-43, -3) -> (-43, -10)
  line L8 (-43, -10) -> (-36, -3)
  point P0 (-51, 6)
  dimension "d146" = 7
  dimension "d147" = 7
  constraints: 12 end point, 2 horizontal, 2 perpendicular
  measures "d146" distance of L0.start L3.end
  measures "d147" distance of L6.end L7.end
extrude "Extrusion33" add sketch "Sketch35" against normal up to surface (21 mm away)
body "Solid1"
